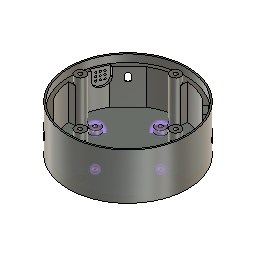
PCB BASE 3D (Autodesk Fusion 360 archive; units mm, degrees)
design "BOTTOM LIGHT BASE"
part number: 2026-05-20-15-01-53-421
Autodesk Fusion 360 part; units mm, degrees
sketch "Sketch1" plane through (0, 0, 0) normal (0, 0, 1) x (1, 0, 0)
  circle A0 centre (0, 0) radius 40
  circle A1 centre (0, 0) radius 39
  dimension "d1" = 80
  dimension "d2" = -1
  constraint coincident A0.centre A1.centre
  measures "d1" diameter of A0
extrude "Extrude1" add sketch "Sketch1" along normal blind 31
sketch "Sketch2" plane through (0, 0, 0) normal (0, 0, 1) x (1, 0, 0)
  circle A0 centre (0, 0) radius 39
  circle A1 centre (0, 0) radius 36.5
  dimension "d5" = 78
  dimension "d6" = 73
  constraint coincident A0.centre A1.centre
  measures "d5" diameter of A0
  measures "d6" diameter of A1
extrude "Extrude2" add sketch "Sketch2" along normal blind 2.5 contours A0 | A1
extrude "Extrude3" add sketch "Sketch2" along normal blind 23.5 from surface at 2.5
sketch "Sketch3" plane through (0, 0, 2.5) normal (0, 0, 1) x (-1, 0, 0)
  circle A0 centre (0, 0) radius 36.5
  circle A1 centre (0, 22) radius 3.5
  circle A2 centre (0, 22) radius 1.25
  circle A3 centre (-22, 0) radius 1.25
  circle A4 centre (-22, 0) radius 3.5
  circle A5 centre (0, -22) radius 1.25
  circle A6 centre (0, -22) radius 3.5
  circle A7 centre (22, 0) radius 1.25
  circle A8 centre (22, 0) radius 3.5
  dimension "d12" = 7
  dimension "d13" = 2.5
  dimension "d14" = 22
  dimension "d16" = 360
  constraint concentric A1 A2
  constraint vertical A0.centre A1.centre
  measures "d12" diameter of A1
  measures "d13" diameter of A2
  measures "d14" distance of A0.centre A1.centre
extrude "Extrude4" add sketch "Sketch3" along normal blind 3 contours A1 | A4 | A6 | A8
sketch "Sketch4" plane through (0, 0, 2.5) normal (0, 0, 1) x (-1, 0, 0)
  circle A0 centre (0, 22) radius 3.5
  circle A1 centre (-22, 0) radius 3.5
  circle A2 centre (0, 0) radius 36.5
  circle A3 centre (0, -22) radius 3.5
  circle A4 centre (22, 0) radius 3.5
  circle A5 centre (0, 32) radius 3.5
  circle A6 centre (0, 32) radius 1.25
  circle A7 centre (-32, 0) radius 3.5
  circle A8 centre (-32, 0) radius 1.25
  circle A9 centre (0, -32) radius 3.5
  circle A10 centre (0, -32) radius 1.25
  circle A11 centre (32, 0) radius 3.5
  circle A12 centre (32, 0) radius 1.25
  line L0 (3.5, 32) -> (3.5, 36.3318)
  line L1 (-3.4971, 32.1421) -> (-3.3213, 36.4703)
  line L2 (-3.5, -32) -> (-3.5, -36.3318)
  line L3 (3.5, -32) -> (3.5, -36.3318)
  line L4 (-31.9802, 3.4999) -> (-36.3294, 3.5245)
  line L5 (-31.9802, -3.4999) -> (-36.3294, -3.5245)
  line L6 (32, 3.5) -> (36.3318, 3.5)
  line L7 (32, -3.5) -> (36.3318, -3.5)
  dimension "d19" = 7
  dimension "d20" = 2.5
  dimension "d21" = 32
  dimension "d23" = 360
  constraint concentric A5 A6
  constraint vertical A2.centre A5.centre
  constraint coincident A5 L0.start
  constraint coincident A2 L0.end
  constraint vertical L0
  constraint coincident A5 L1.start
  constraint tangent A5 L1
  constraint tangent A5 L0
  constraint equal L0 L1
  constraint coincident A9 L2.start
  constraint coincident A2 L2.end
  constraint vertical L2
  constraint coincident A9 L3.start
  constraint coincident A2 L3.end
  constraint parallel L2 L3
  constraint tangent A9 L2
  constraint tangent A9 L3
  constraint coincident A7 L4.start
  constraint coincident A2 L4.end
  constraint tangent A7 L4
  constraint coincident A7 L5.start
  constraint coincident A2 L5.end
  constraint tangent A7 L5
  constraint coincident A11 L6.start
  constraint coincident A2 L6.end
  constraint horizontal L6
  constraint coincident A11 L7.start
  constraint coincident A2 L7.end
  constraint tangent A11 L7
  constraint tangent A11 L6
  constraint equal L6 L7
  constraint equal L4 L5
  measures "d19" diameter of A5
  measures "d20" diameter of A6
  measures "d21" vertical distance of A2.centre A5.centre
extrude "Extrude5" add sketch "Sketch4" along normal blind 28.5 contours A11 | A5 | A9 | A7
extrude "Extrude6" add sketch "Sketch4" along normal blind 23.5 contours A2 A11 L6 L7 | A2 A5 L0 L1 | A2 A9 L2 L3 | A2 A7 L4 L5
sketch "Sketch5" plane through (0, 0, 26) normal (0, 0, 1) x (-1, 0, 0)
  arc A0 (-36.3294, -3.5245) -> (-3.5, -36.3318) centre (0, 0) ccw
  line L0 (-36.3294, -3.5245) -> (-31.9802, -3.4999)
  arc A1 (-31.9802, 3.4999) -> (-31.9802, -3.4999) centre (-32, 0) ccw
  line L1 (-31.9802, 3.4999) -> (-36.3294, 3.5245)
  arc A2 (-3.3262, 36.3481) -> (-36.3294, 3.5245) centre (0, 0) ccw
  line L2 (-3.3262, 36.3481) -> (-3.4971, 32.1421)
  arc A3 (3.5, 32) -> (-3.4971, 32.1421) centre (0, 32) ccw
  line L3 (3.5, 32) -> (3.5, 36.3318)
  arc A4 (36.3318, 3.5) -> (3.5, 36.3318) centre (0, 0) ccw
  line L4 (36.3318, 3.5) -> (32, 3.5)
  arc A5 (32, -3.5) -> (32, 3.5) centre (32, 0) ccw
  line L5 (32, -3.5) -> (36.3318, -3.5)
  arc A6 (3.5, -36.3318) -> (36.3318, -3.5) centre (0, 0) ccw
  line L6 (3.5, -36.3318) -> (3.5, -32)
  arc A7 (-3.5, -32) -> (3.5, -32) centre (0, -32) ccw
  line L7 (-3.5, -32) -> (-3.5, -36.3318)
  circle A8 centre (0, 0) radius 39
  line L8 (18.7432, -31.32) -> (31.3167, -18.7487)
  line L9 (18.7432, 31.32) -> (31.3167, 18.7487)
  line L10 (0, 0) -> (0, -5) construction
  line L11 (-18.7432, -31.32) -> (-31.3167, -18.7487)
  dimension "d28" = 17.78
  dimension "d29" = 16.046
  dimension "d30" = 17.78
  dimension "d31" = 16.046
  dimension "d32" = 5
  constraint coincident A6 L8.start
  constraint coincident A6 L8.end
  constraint coincident A4 L9.start
  constraint coincident A4 L9.end
  constraint coincident A0.centre A2.centre
  constraint vertical L10
  constraint symmetric L8.start L10 L11.start
  constraint symmetric L8.end L10 L11.end
  measures "d28" distance of L8.start L8.end
  measures "d29" distance of A6.start L8.start
  measures "d30" distance of L9.start L9.end
  measures "d31" distance of L3.end L9.start
  measures "d32" distance of A0.centre L10.end
extrude "Extrude7" add sketch "Sketch5" against normal up to surface (23.5 mm away) contours A0 L11 | A6 L8 | A4 L9
sketch "Sketch6" plane through (-25.03, -25.0344, 0) normal (0.707045, 0.707169, 0) x (-0.707169, 0.707045, 0)
  line L0 (-8.89, 2.5) -> (8.89, 2.5)
  line L1 (8.89, 2.5) -> (8.89, 26)
  line L2 (8.89, 26) -> (-8.89, 26)
  line L3 (-8.89, 26) -> (-8.89, 2.5)
  circle A0 centre (0, 13.5) radius 4.5
  line L4 (40, 0) -> (-40, 0)
  dimension "d35" = 9
  dimension "d36" = 13.5
  measures "d35" diameter of A0
  measures "d36" distance of A0.centre L4
extrude "Extrude8" cut sketch "Sketch6" against normal blind 60 contours A0
sketch "Sketch7" plane through (-25.03, 25.0344, 0) normal (0.707045, -0.707169, 0) x (0.707169, 0.707045, 0)
  line L0 (-8.89, 2.5) -> (8.89, 2.5)
  line L1 (8.89, 2.5) -> (8.89, 26)
  line L2 (8.89, 26) -> (-8.89, 26)
  line L3 (-8.89, 26) -> (-8.89, 2.5)
  line L4 (-1.722, 21.0095) -> (-1.722, 18.9905)
  arc A0 (-1.722, 18.9905) -> (1.759, 18.9905) centre (0.0185, 18.9905) ccw
  line L5 (1.759, 18.9905) -> (1.759, 21.0095)
  arc A1 (1.759, 21.0095) -> (-1.722, 21.0095) centre (0.0185, 21.0095) ccw
  line L6 (0.0185, 21.0095) -> (0.0185, 18.9905) construction
  dimension "d39" = 5.5
  dimension "d40" = 3.481
  dimension "d41" = 14.75
  dimension "d42" = 7.131
  constraint tangent L4 A0
  constraint tangent A0 L5
  constraint parallel L4 L5
  constraint tangent L5 A1
  constraint tangent L4 A1
  constraint vertical L6
  measures "d40" distance of L4.start L5.end
  measures "d41" distance of L0 A0
  measures "d42" distance of L1 A0.end
extrude "Extrude9" cut sketch "Sketch7" against normal blind 0.698 contours L4 A0 L5 A1
extrude "Extrude10" cut sketch "Sketch7" against normal through all draft 37 from surface at -0.698 contours L4 A0 L5 A1
sketch "Sketch8" plane through (25.03, 25.0344, 0) normal (-0.707045, -0.707169, 0) x (0.707169, -0.707045, 0)
  line L0 (-8.89, 2.5) -> (8.89, 2.5)
  line L1 (8.89, 2.5) -> (8.89, 26)
  line L2 (8.89, 26) -> (-8.89, 26)
  line L3 (-8.89, 26) -> (-8.89, 2.5)
  circle A0 centre (0, 11) radius 3.75
  line L4 (40, 0) -> (-40, 0)
  line L5 (11.25, 11) -> (-3.75, 11)
  line L6 (3.75, 11) -> (3.75, 26)
  line L7 (-3.75, 11) -> (-3.75, 26)
  point P0 (3.75, 11)
  dimension "d47" = 7.5
  dimension "d48" = 11
  constraint vertical origin A0.centre
  constraint midpoint L5 P0
  constraint coincident A0 P0
  constraint coincident A0 L5.end
  constraint horizontal L5
  constraint coincident P0 L6.start
  constraint coincident L2 L6.end
  constraint perpendicular L2 L6
  constraint coincident L2 L7.end
  constraint perpendicular L2 L7
  constraint tangent A0 L7
  measures "d47" diameter of A0
  measures "d48" distance of A0.centre L4
extrude "Extrude11" cut sketch "Sketch8" against normal blind 2.6 contours L2 A0 L6 L7 | A0 L5 | A0 L5
extrude "Extrude12" cut sketch "Sketch8" against normal through all contours A0 L5 | A0 L5
sketch "Sketch9" plane through (0, 0, 26) normal (0, 0, 1) x (-1, 0, 0)
  line L0 (-29.5202, -24.2216) -> (-27.6818, -22.3829)
  line L1 (-27.6818, -22.3829) -> (-31.3167, -18.7487)
  arc A0 (-36.3294, -3.5245) -> (-31.3167, -18.7487) centre (0, 0) ccw
  line L2 (-36.3294, -3.5245) -> (-31.9802, -3.4999)
  arc A1 (-31.9802, 3.4999) -> (-31.9802, -3.4999) centre (-32, 0) ccw
  line L3 (-31.9802, 3.4999) -> (-36.3294, 3.5245)
  arc A2 (-3.3262, 36.3481) -> (-36.3294, 3.5245) centre (0, 0) ccw
  line L4 (-3.3262, 36.3481) -> (-3.4971, 32.1421)
  arc A3 (3.5, 32) -> (-3.4971, 32.1421) centre (0, 32) ccw
  line L5 (3.5, 32) -> (3.5, 36.3318)
  arc A4 (18.7432, 31.32) -> (3.5, 36.3318) centre (0, 0) ccw
  line L6 (18.7432, 31.32) -> (31.3167, 18.7487)
  arc A5 (36.3318, 3.5) -> (31.3167, 18.7487) centre (0, 0) ccw
  line L7 (36.3318, 3.5) -> (32, 3.5)
  arc A6 (32, -3.5) -> (32, 3.5) centre (32, 0) ccw
  line L8 (32, -3.5) -> (36.3318, -3.5)
  arc A7 (31.3167, -18.7487) -> (36.3318, -3.5) centre (0, 0) ccw
  line L9 (31.3167, -18.7487) -> (18.7432, -31.32)
  arc A8 (3.5, -36.3318) -> (18.7432, -31.32) centre (0, 0) ccw
  line L10 (3.5, -36.3318) -> (3.5, -32)
  arc A9 (-3.5, -32) -> (3.5, -32) centre (0, -32) ccw
  line L11 (-3.5, -32) -> (-3.5, -36.3318)
  arc A10 (-18.7432, -31.32) -> (-3.5, -36.3318) centre (0, 0) ccw
  line L12 (-18.7432, -31.32) -> (-22.3781, -27.6858)
  line L13 (-22.3781, -27.6858) -> (-24.2164, -29.5244)
  line L14 (-24.2164, -29.5244) -> (-29.5202, -24.2216)
  circle A11 centre (0, 0) radius 39
  line L15 (32.1385, -20.5117) -> (36.4457, -10.9357)
  line L16 (32.1385, -20.5117) -> (30.3555, -19.7097)
  line L17 (36.4457, -10.9357) -> (35.0184, -10.2938)
  dimension "d52" = 10.5
  dimension "d53" = 17.212
  dimension "d54" = 1.955
  dimension "d55" = 1.565
  constraint coincident L9 L16.end
  constraint perpendicular L15 L16
  constraint coincident A7 L17.end
  constraint perpendicular L15 L17
  measures "d52" distance of L15.start L15.end
  measures "d53" distance of L9.end L15.start
  measures "d54" distance of L15.start L16.end
  measures "d55" distance of L15.end L17.end
extrude "Extrude13" cut sketch "Sketch9" against normal blind 5.8 contours A7 L9 L15 L16 L17
ref_plane "WorkPlane1" through (-30.3555, 19.7097, 26) normal (0.938263, -0.345923, 0) x (0.345923, 0.938263, 0)
sketch "Sketch10" plane through (-33.1202, 12.2109, 0) normal (0.938263, -0.345923, 0) x (0.345923, 0.938263, 0)
  line L0 (7.9922, 26) -> (7.9922, 20.2)
  line L1 (7.9922, 20.2) -> (6.7581, 20.2)
  line L2 (6.7581, 20.2) -> (-2.4554, 20.2)
  line L3 (-2.4554, 20.2) -> (-2.4554, 26)
  arc A0 (-2.4554, 20.2) -> (7.9922, 20.2) centre (2.7684, 20.2) ccw
  constraint tangent L0 A0
  constraint coincident L0.end L1.start
  constraint coincident L2.end L3.start
extrude "Extrude14" cut sketch "Sketch10" along normal up to surface end surface through (-32.1385, 20.5117, 26) normal (0.911992, -0.410207, 0) offset 0
sketch "Sketch11" plane through (-34.4041, 15.4747, 0) normal (0.911992, -0.410207, 0) x (0.410207, 0.911992, 0)
  line L0 (5.523, 26) -> (-4.977, 26)
  line L1 (-4.977, 26) -> (-4.977, 20.2)
  line L2 (-4.977, 20.2) -> (-5.0858, 20.2)
  ellipse E0 centre (0.1506, 20.2) end of major axis (-5.0858, 20.2) minor radius 5.2238 (-5.0858, 20.2) -> (5.387, 20.2) ccw
  line L3 (5.387, 20.2) -> (5.523, 20.2)
  line L4 (5.523, 20.2) -> (5.523, 26)
  circle A0 centre (2.622, 23.4) radius 0.6
  circle A1 centre (0.304, 23.4) radius 0.6
  circle A2 centre (-2.014, 23.4) radius 0.6
  circle A3 centre (2.622, 20.9) radius 0.6
  circle A4 centre (0.304, 20.9) radius 0.6
  circle A5 centre (-2.014, 20.9) radius 0.6
  circle A6 centre (2.622, 18.4) radius 0.6
  circle A7 centre (0.304, 18.4) radius 0.6
  circle A8 centre (-2.014, 18.4) radius 0.6
  dimension "d60" = 1.2
  dimension "d61" = 2.6
  dimension "d62" = 2.901
  dimension "d65" = -4.636
  dimension "d66" = 0
  dimension "d69" = 0
  dimension "d70" = -5
  measures "d60" diameter of A0
  measures "d61" distance of L0 A0.centre
  measures "d62" distance of L4 A0.centre
extrude "Extrude15" cut sketch "Sketch11" against normal through all contours A0 | A1 | A2 | A3 | A4 | A5 | A6 | A7 | A8
sketch "Sketch12" plane through (0, 0, 2.5) normal (0, 0, 1) x (-1, 0, 0)
  line L0 (31.3167, 18.7487) -> (18.7432, 31.32)
  arc A0 (18.7432, 31.32) -> (3.5, 36.3318) centre (0, 0) ccw
  line L1 (3.5, 36.3318) -> (3.5, 32)
  arc A1 (-3.4971, 32.1421) -> (3.5, 32) centre (0, 32) ccw
  line L2 (-3.4971, 32.1421) -> (-3.3262, 36.3481)
  arc A2 (-3.3262, 36.3481) -> (-36.3294, 3.5245) centre (0, 0) ccw
  line L3 (-36.3294, 3.5245) -> (-31.9802, 3.4999)
  arc A3 (-31.9802, -3.4999) -> (-31.9802, 3.4999) centre (-32, 0) ccw
  line L4 (-31.9802, -3.4999) -> (-36.3294, -3.5245)
  arc A4 (-36.3294, -3.5245) -> (-31.3167, -18.7487) centre (0, 0) ccw
  line L5 (-31.3167, -18.7487) -> (-18.7432, -31.32)
  arc A5 (-18.7432, -31.32) -> (-3.5, -36.3318) centre (0, 0) ccw
  line L6 (-3.5, -36.3318) -> (-3.5, -32)
  arc A6 (3.5, -32) -> (-3.5, -32) centre (0, -32) ccw
  line L7 (3.5, -32) -> (3.5, -36.3318)
  arc A7 (3.5, -36.3318) -> (18.7432, -31.32) centre (0, 0) ccw
  line L8 (18.7432, -31.32) -> (31.3167, -18.7487)
  arc A8 (31.3167, -18.7487) -> (36.3318, -3.5) centre (0, 0) ccw
  line L9 (36.3318, -3.5) -> (32, -3.5)
  arc A9 (32, 3.5) -> (32, -3.5) centre (32, 0) ccw
  line L10 (32, 3.5) -> (36.3318, 3.5)
  arc A10 (36.3318, 3.5) -> (31.3167, 18.7487) centre (0, 0) ccw
  circle A11 centre (0, 22) radius 3.5
  circle A12 centre (-22, 0) radius 3.5
  circle A13 centre (0, -22) radius 3.5
  circle A14 centre (22, 0) radius 3.5
  circle A15 centre (0, -22) radius 1.25
  circle A16 centre (-22, 0) radius 1.25
  circle A17 centre (22, 0) radius 1.25
  circle A18 centre (0, 22) radius 1.25
